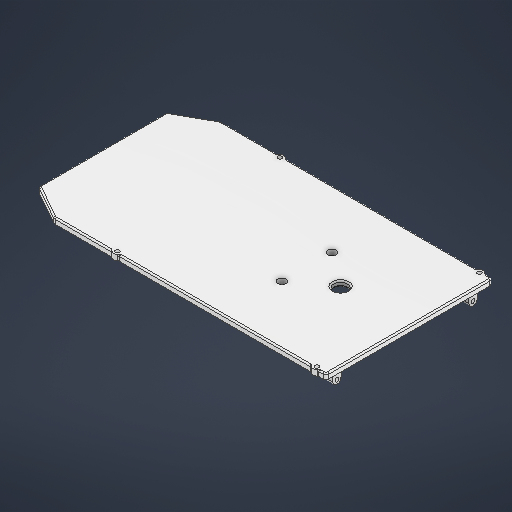
# Autodesk Inventor part: Крышка_верхняя
Saved by Autodesk Inventor 2026 (Build 300175050, 175E)
## iProperties
Created: 2026-10-25
Part Number: Крышка_верхняя
Material: Пластик АБС
Document SubType Name: Modeling
Designer: VK7
Density: 1.06 g/cm^3
Appearance: Гладкий — белый
Author: VK7
## iProperties of the stored document Крышка_верхняя_3DПЕЧАТЬ.ipt
Created: 2026-11-08
Part Number: Крышка_верхняя_3DПЕЧАТЬ
Material: Типовые
Document SubType Name: Modeling
Designer: VK7
Density: 1 g/cm^3
Appearance: По умолчанию
Author: VK7
Autodesk Inventor part; units mm, degrees
sketch "Эскиз1" plane through (0, 0, 0) normal (0, 1, 0) x (-1, 0, 0)
  line L0 (0, 0) -> (195.75, 0)
  line L1 (195.75, 0) -> (195.75, -120)
  line L2 (195.75, -120) -> (0, -120)
  line L3 (0, -120) -> (0, 0)
  line L4 (195.75, 0) -> (220.75, 0)
  line L5 (195.75, 0) -> (220.75, -14.0064)
  line L6 (195.75, 0) -> (224.4062, 0) construction
  line L7 (195.75, -60) -> (205.75, -60)
  line L8 (195.75, -120) -> (220.75, -105.9936)
  line L9 (220.75, -14.0064) -> (220.75, -105.9936)
  dimension "d0" = 195.75
  dimension "d1" = 120
  dimension "d2" = 25
  dimension "d3" = 29.26
  dimension "d4" = 10
  dimension "d5" = 91.9872
  constraints: 20 end point, 4 horizontal, 2 parallel, 1 equal length, 1 midpoint, 1 perpendicular, 1 symmetric about line, 1 vertical
  measures "d0" distance of L1.end L2.end
  measures "d1" distance of L0.end L1.end
  measures "d2" distance of L0.end L4.end
  measures "d3" angle of L5 L6
  measures "d4" distance of L7.start L7.end
  measures "d5" distance of L5.end L8.end
extrude "Выдавливание1" add sketch "Эскиз1" along normal blind 3
sketch "Эскиз2" plane through (0, 3, 0) normal (0, 1, 0) x (1, 0, 0)
  line L0 (0, 0) -> (0, 120) projected
  line L1 (0, 0) -> (0, 1.5)
  line L2 (0, 1.5) -> (-8, 1.5)
  circle A0 centre (-8, 1.5) radius 1.5
  circle A1 centre (-8, 1.5) radius 2
  line L3 (0, 1.5) -> (-151.75, 1.5)
  circle A2 centre (-151.75, 1.5) radius 1.5
  circle A3 centre (-151.75, 1.5) radius 2
  line L4 (0, 60) -> (-5, 60)
  circle A4 centre (-8, 118.5) radius 1.5
  circle A5 centre (-8, 118.5) radius 2
  circle A6 centre (-151.75, 118.5) radius 1.5
  circle A7 centre (-151.75, 118.5) radius 2
  dimension "d8" = 1.5
  dimension "d9" = 8
  dimension "d10" = 3
  dimension "d11" = 4
  dimension "d12" = 151.75
  dimension "d14" = 3
  dimension "d15" = 4
  dimension "d16" = 5
  constraints: 8 centre point, 8 end point, 6 coincident, 4 symmetric about line, 2 horizontal, 1 midpoint, 1 perpendicular, 1 point on line, 4 other
  measures "d8" distance of L0.start L1.end
  measures "d9" distance of L1.end L2.end
  measures "d10" diameter of A0
  measures "d11" diameter of A1
  measures "d12" distance of L1.end L3.end
  measures "d14" diameter of A2
  measures "d15" diameter of A3
  measures "d16" distance of L4.start L4.end
extrude "Выдавливание2" add sketch "Эскиз2" against normal blind 3 contours A1 L3 A0 L2 | L2 A0 L3 A1 | A3 | A5 | A7
extrude "Выдавливание3" cut sketch "Эскиз2" against normal blind 3 contours A0 L3 L2 | L2 L3 A0 | A2 | A4 | A6
fillet "Сопряжение1" radius 1 8 edges at (-153.0729, 1.5, 0) (-150.4271, 1.5, 0) (-9.3229, 1.5, 0) (-6.6771, 1.5, 0) (-6.6771, 1.5, -120) (-9.3229, 1.5, -120) (-150.4271, 1.5, -120) (-153.0729, 1.5, -120)
sketch "Эскиз3" plane through (0, 0, 0) normal (0, -1, 0) x (1, 0, 0)
  line L0 (0, 0) -> (0, -120) projected
  line L1 (0, -60) -> (-73.75, -60)
  line L2 (-73.75, -60) -> (-73.75, -78)
  circle A0 centre (-73.75, -78) radius 3
  circle A1 centre (-73.75, -42) radius 3
  dimension "d22" = 73.75
  dimension "d23" = 18
  dimension "d24" = 6
  constraints: 4 end point, 2 centre point, 1 coincident, 1 horizontal, 1 midpoint, 1 symmetric about line, 1 vertical, 1 other
  measures "d22" distance of L1.start L1.end
  measures "d23" distance of L1.end L2.end
  measures "d24" diameter of A0
extrude "Выдавливание4" cut sketch "Эскиз3" against normal blind 3
sketch "Эскиз4" plane through (0, 0, 0) normal (0, -1, 0) x (1, 0, 0)
  line L0 (0, 0) -> (0, -120) projected
  line L1 (0, -60) -> (-97.35, -60)
  line L2 (-97.35, -60) -> (-97.35, -27)
  circle A0 centre (-97.35, -27) radius 4.1
  circle A1 centre (-97.35, -27) radius 7.1
  line L3 (-93.25, -27) -> (-88.25, -27)
  line L4 (-97.35, -34.1) -> (-88.25, -34.1)
  line L5 (-88.25, -34.1) -> (-88.25, -27)
  line L6 (-97.35, -27) -> (-97.35, -19.9)
  line L7 (-97.35, -19.9) -> (-88.25, -19.9)
  line L8 (-88.25, -19.9) -> (-88.25, -27)
  dimension "d29" = 8.2
  dimension "d27" = 97.35
  dimension "d28" = 33
  dimension "d30" = 14.2
  dimension "d32" = 5
  constraints: 16 end point, 4 perpendicular, 3 horizontal, 2 coincident, 2 point on circle, 1 centre point, 1 horizontal alignment, 1 midpoint, 1 point on line, 1 tangent, 1 vertical, 2 other
  measures "d27" distance of L1.start L1.end
  measures "d28" distance of L1.end L2.end
  measures "d30" diameter of A1
  measures "d32" distance of L3.start L3.end
extrude "Выдавливание5" add sketch "Эскиз4" along normal blind 20 contours A1 L6 A0 L2 | L2 A0 L3 A1 | A1 L3 L5 L4 | L7 L8 L3 A1 | A1 L3 A0 L6
ref_plane "РабПлоскость1" through (-97.35, 0, -19.9) normal (1, 0, 0) x (0, 0, -1)
sketch "Эскиз5" plane through (-97.35, 0, -19.9) normal (1, 0, 0) x (0, 0, -1)
  line L0 (0, -20) -> (14.2, -20) projected
  line L1 (7.1, -20) -> (7.1, -10)
  line L2 (7.1, -10) -> (7.1, -12.8)
  line L3 (7.1, -12.8) -> (9.1, -12.8)
  line L4 (9.1, -12.8) -> (5.1, -12.8)
  line L5 (9.5249, -11.4) -> (10.5249, -9.6679)
  line L6 (10.5249, -9.6679) -> (8.5249, -13.1321)
  line L7 (9.5249, -8.6) -> (8.5249, -6.8679)
  line L8 (8.5249, -6.8679) -> (10.5249, -10.3321)
  line L9 (7.1, -7.2) -> (5.1, -7.2)
  line L10 (5.1, -7.2) -> (9.1, -7.2)
  line L11 (4.6751, -8.6) -> (3.6751, -10.3321)
  line L12 (3.6751, -10.3321) -> (5.6751, -6.8679)
  line L13 (4.6751, -11.4) -> (5.6751, -13.1321)
  line L14 (5.6751, -13.1321) -> (3.6751, -9.6679)
  circle A0 centre (7.1, -10) radius 1.45
  point P0 (-19.9, 0)
  point P1 (8.7166, -12.8)
  point P2 (9.5249, -11.4)
  point P3 (10.3332, -10)
  point P4 (9.5249, -8.6)
  point P5 (8.7166, -7.2)
  point P6 (7.1, -7.2)
  point P7 (5.4834, -7.2)
  point P8 (4.6751, -8.6)
  point P9 (3.8668, -10)
  point P10 (4.6751, -11.4)
  point P11 (5.4834, -12.8)
  dimension "d36" = 10
  dimension "d37" = 2.8
  dimension "d38" = 2
  dimension "d39" = 4
  dimension "d42" = 360
  dimension "d44" = 2.9
  constraints: 28 end point, 7 point on line, 1 centre point, 1 coincident, 1 midpoint, 1 perpendicular, 1 vertical, 31 other
  measures "d36" distance of L1.start L1.end
  measures "d37" distance of L1.end L2.end
  measures "d38" distance of L2.end L3.end
  measures "d39" distance of L3.end L4.end
  measures "d44" diameter of A0
extrude "Выдавливание6" cut sketch "Эскиз5" along normal blind 6.8
extrude "Выдавливание7" cut sketch "Эскиз5" along normal blind 10 contours A0
ref_plane "РабПлоскость2" through (-9.6583, 0, -60) normal (0, 0, -1) x (-1, 0, 0)
mirror "Зеркальное отражение1" about plane through (-9.6583, 0, -60) normal (0, 0, -1) of "Выдавливание5", "Выдавливание7", "Выдавливание6"
ref_plane "РабПлоскость3" through (-122.8, 0, -19.9) normal (1, 0, 0) x (0, 0, -1)
mirror "Зеркальное отражение2" about plane through (-122.8, 0, -19.9) normal (1, 0, 0) of "Выдавливание5", "Выдавливание7", "Выдавливание6", "Зеркальное отражение1"
fillet "Сопряжение2" radius 3 4 edges at (-220.75, 1.5, -105.9936) (-195.75, 1.5, -120) (-195.75, 1.5, 0) (-220.75, 1.5, -14.0064)
fillet "Сопряжение4" radius 2 2 edges at (0, 1.5, 0) (0, 1.5, -120)
ref_plane "РабПлоскость4" through (-3.1, 0, -2) normal (1, 0, 0) x (0, 0, -1)
sketch "Эскиз9" plane through (-3.1, 0, -2) normal (1, 0, 0) x (0, 0, -1)
  line L0 (-1.6172, 0) -> (-2, 0) projected
  line L1 (-2, 0) -> (9, 0)
  line L2 (0, 0) -> (116, 0) projected
  line L3 (9, 0) -> (9, -6.5)
  line L4 (9, 0) -> (15.5, 0) construction
  circle A0 centre (9, -6.5) radius 1.45
  circle A1 centre (9, -6.5) radius 2.95
  line L5 (6.05, -6.5) -> (6.05, 0)
  line L6 (11.95, -6.5) -> (11.95, 0)
  line L7 (58, 0) -> (58, -5)
  line L8 (107, 0) -> (107, -6.5)
  line L9 (107, 0) -> (100.5, 0) construction
  circle A2 centre (107, -6.5) radius 1.45
  circle A3 centre (107, -6.5) radius 2.95
  line L10 (109.95, -6.5) -> (109.95, 0)
  line L11 (104.05, -6.5) -> (104.05, 0)
  dimension "d65" = 11
  dimension "d66" = 6.5
  dimension "d67" = 90
  dimension "d68" = 2.9
  dimension "d69" = 5.9
  dimension "d70" = 5
  constraints: 20 end point, 9 symmetric about line, 4 centre point, 4 coincident, 4 perpendicular, 4 point on circle, 4 point on line, 2 tangent, 1 horizontal, 1 midpoint, 1 vertical, 2 other
  measures "d65" distance of L0.end L1.end
  measures "d66" distance of L1.end L3.end
  measures "d67" angle of L3 L4
  measures "d68" diameter of A0
  measures "d69" diameter of A1
  measures "d70" distance of L7.start L7.end
extrude "Выдавливание10" add sketch "Эскиз9" against normal blind 10.5
sketch "Эскиз10" plane through (-13.6, 0, -2) normal (-1, 0, 0) x (0, 0, 1)
  circle A0 centre (-9, -6.5) radius 1.45 projected
  circle A1 centre (-107, -6.5) radius 1.45 projected
  point P0 (2, 0)
extrude "Выдавливание11" add sketch "Эскиз10" against normal blind 1
fillet "Сопряжение7" radius 1 6 edges at (-8.35, 0, -106.05) (-8.35, 0, -111.95) (-8.35, 0, -8.05) (-8.35, 0, -13.95) (-13.6, 0, -11) (-13.6, 0, -109)
sketch "Эскиз13" plane through (0, 0, 0) normal (0, -1, 0) x (1, 0, 0)
  line L0 (0, -2) -> (0, -118) projected
  line L1 (0, -60) -> (-49.5, -60)
  circle A0 centre (-49.5, -60) radius 5
  point P0 (0, 0)
  dimension "d97" = 49.5
  dimension "d98" = 10
  constraints: 2 end point, 1 centre point, 1 coincident, 1 horizontal, 1 midpoint
  measures "d97" distance of L1.start L1.end
  measures "d98" diameter of A0
extrude "Выдавливание13" cut sketch "Эскиз13" against normal blind 10
sketch "Эскиз14" plane through (0, 0, 0) normal (0, -1, 0) x (1, 0, 0)
  circle A0 centre (-8, -1.5) radius 1.5 projected
  circle A1 centre (-8, -1.5) radius 2.75
  arc A2 (-150.25, -1.5) -> (-150.25, -1.5) centre (-151.75, -1.5) ccw projected
  circle A3 centre (-151.75, -1.5) radius 2.75
  arc A4 (-9.1055, -120.1667) -> (-6.8945, -120.1667) centre (-8, -118.5) ccw projected
  circle A5 centre (-8, -118.5) radius 2.75
  circle A6 centre (-151.75, -118.5) radius 1.5 projected
  circle A7 centre (-151.75, -118.5) radius 2.75
  circle A8 centre (-151.75, -1.5) radius 1.5 projected
  circle A9 centre (-8, -118.5) radius 1.5 projected
  point P0 (0, 0)
  dimension "d102" = 5.5
  dimension "d103" = 5.5
  dimension "d104" = 5.5
  dimension "d105" = 5.5
  constraints: 4 centre point, 4 coincident
  measures "d102" diameter of A1
  measures "d103" diameter of A3
  measures "d104" diameter of A5
  measures "d105" diameter of A7
move faces "Перенос1" translate (0, 1, 0) faces at (-126.3663, 3, -65.7607)
extrude "Выдавливание15" add sketch "Эскиз14" against normal blind 4
fillet "Сопряжение9" radius 1 16 edges at (-0.5858, 4, -119.4142) (-3.8476, 4, -120) (-0.5858, 4, -0.5858) (-3.8476, 4, 0) (0, 4, -60) (-79.875, 4, -120) (-195.7246, 4, -119.9027) (-207.8248, 4, -113.235) (-220.3383, 4, -105.7524) (-220.75, 4, -60) (-220.3383, 4, -14.2476) (-207.8248, 4, -6.765) (-195.7246, 4, -0.0973) (-174.5109, 4, 0) (-174.5109, 4, -120) (-79.875, 4, 0)
fillet "Сопряжение10" radius 1 16 edges at (-5.6951, 1.5, -120) (-5.5408, 3.6825, -119.7309) (-10.4592, 3.6826, -119.7308) (-10.3049, 1.5, -120) (-149.4451, 1.5, -120) (-149.2908, 3.6826, -119.7308) (-154.0549, 1.5, -120) (-154.2092, 3.6826, -119.7308) (-5.6951, 1.5, 0) (-5.5408, 3.6826, -0.2692) (-10.3049, 1.5, 0) (-10.4592, 3.6826, -0.2692) (-154.0549, 1.5, 0) (-154.2092, 3.6826, -0.2692) (-149.2908, 3.6826, -0.2692) (-149.4451, 1.5, 0)
fillet "Сопряжение11" radius 1 2 edges at (-54.5, 0, -60) (-54.5, 4, -60)
fillet "Сопряжение12" radius 3 16 edges at (-88.25, 0, -93) (-104.45, 0, -93) (-92.8, 0, -100.1) (-92.8, 0, -85.9) (-152.8, 0, -100.1) (-152.8, 0, -85.9) (-141.15, 0, -93) (-157.35, 0, -93) (-157.35, 0, -27) (-141.15, 0, -27) (-152.8, 0, -34.1) (-152.8, 0, -19.9) (-88.25, 0, -27) (-104.45, 0, -27) (-92.8, 0, -34.1) (-92.8, 0, -19.9)
